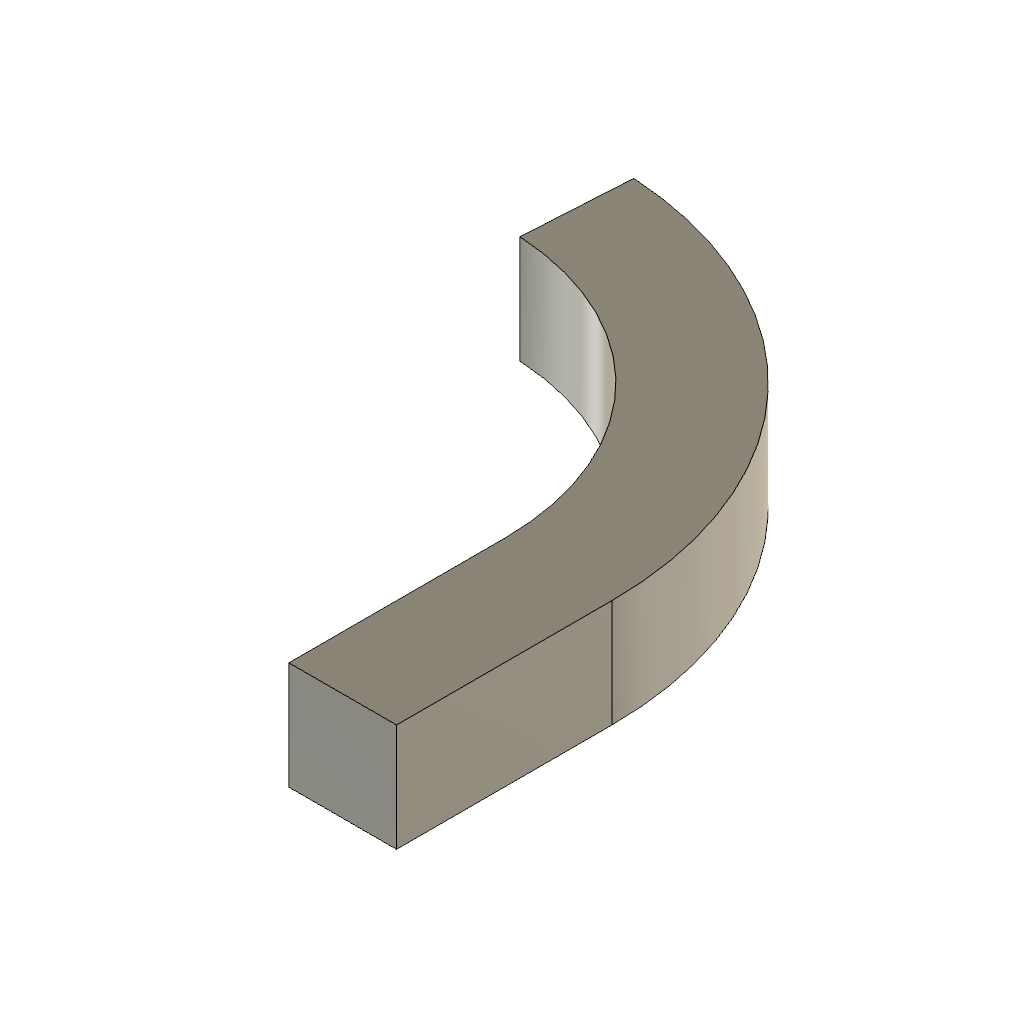
vendor_SweepHook (Autodesk Fusion 360 design; units mm, degrees)
Autodesk Fusion 360 part; units mm, degrees
sketch "Sweep profile" plane through (0, 0, 0) normal (0, 1, 0) x (1, 0, 0)
  line L0 (-5, 0) -> (5, 0)
  line L1 (5, 0) -> (5, -10)
  line L2 (5, -10) -> (-5, -10)
  line L3 (-5, -10) -> (-5, 0)
sketch "Sweep path" plane through (0, 0, 0) normal (0, 0, 1) x (1, 0, 0)
  line L0 (0, 0) -> (0, 20)
  arc A0 (0, 20) -> (-30, 50) centre (-30, 20) ccw
  line L1 (-30, 50) -> (-50, 50)
sweep "Bend sweep" add profiles "Sweep profile" path "Sweep path" along L0 A0 L1 for 0.75 of its length starting at (0, 0, 0) heading (0, 1, 0) section 1
equation "height = 20.0 mm"
